360001_P01_FRONT-DOOR-UNIT_CAD (Autodesk Fusion 360 design; units mm, degrees)
part number: 2026-10-31-21-38-45-586
description: FRONT - DOOR LEAF - 4+4 LAMINATED | Tấm kính cửa 4+4 | P01
part number: 361001
description: FRONT - DOOR KICK STRIP | Thanh chân cửa nhôm | P01
part number: 361002
description: FRONT - GLAZING U-SEAL - BOHLE BO5201735 | Gioăng chữ U silicone | P01
part number: 368002
description: FRONT - DROP SEAL - ATHMER SCHALL-EX GSA 1-1112 | Ron chân cửa tự động | P01
part number: 368001
description: FRONT - DOOR HINGE - HOLD - H1 BOTTOM | Bản lề cửa dưới (chờ chọn) | P01
part number: 368101
description: FRONT - DOOR HINGE - HOLD - H2 MIDDLE | Bản lề cửa giữa (chờ chọn) | P01
description: FRONT - DOOR HINGE - HOLD - H3 TOP | Bản lề cửa trên (chờ chọn) | P01
description: FRONT - DOOR STRIKE - ENVELOPE | Đế hít cửa | P01
part number: 368102
description: FRONT - 180 MAGNETIC SEAL - HALF 2 OF 2 - HOLD | Gioăng nam châm 180° phía cửa (chờ chọn) | P01
part number: 368006
description: FRONT - DOOR PULL PAIR - HOLD | Tay nắm cửa (chờ chọn) | P01
part number: 368103
Autodesk Fusion 360 part; units mm, degrees
sketch "OUTLINE - DOOR LEAF (SKELETON TRAPEZOID + 25 MM INTO THE KICK STRIP)" plane through (0, 0, 0) normal (0, 1, 0) x (1, 0, 0) in component "361001 FRONT - DOOR LEAF - 4+4 LAMINATED"
  line L0 (-961, -80) -> (214, -80)
  line L1 (214, -80) -> (214, -105)
  line L2 (214, -105) -> (-67.7195, -2114)
  line L3 (-67.7195, -2114) -> (-961, -2114)
  line L4 (-961, -2114) -> (-961, -80)
  point P0 (-5000, 5000)
  dimension "d1096" = 5000
  dimension "d1097" = 5000
  dimension "d1098" = 5214
  dimension "d1099" = 4932.2805
  dimension "d1100" = 4039
  constraint vertical L1
  constraint vertical L4
  constraint horizontal L0
  constraint horizontal L3
  measures "d1096" horizontal distance of origin P0
  measures "d1097" vertical distance of origin P0
  measures "d1098" horizontal distance of L0.end P0
  measures "d1099" horizontal distance of L2.end P0
  measures "d1100" horizontal distance of L3.end P0
extrude "EXTRUDE - DOOR LEAF 8.76" add sketch "OUTLINE - DOOR LEAF (SKELETON TRAPEZOID + 25 MM INTO THE KICK STRIP)" along normal blind 8.76 from surface at -703.38 makes body 1 in component "361001 FRONT - DOOR LEAF - 4+4 LAMINATED"
sketch "SECTION - KICK STRIP (H: GLAZING POCKET OVER DROP-SEAL CAVITY)" plane through (0, 0, 0) normal (1, 0, 0) x (0, 0, -1) in component "361002 FRONT - DOOR KICK STRIP"
  line L0 (-20, -709) -> (-20, -705)
  line L1 (-20, -705) -> (-75, -705)
  line L2 (-75, -705) -> (-75, -693)
  line L3 (-75, -693) -> (-20, -693)
  line L4 (-20, -693) -> (-20, -689)
  line L5 (-20, -689) -> (-105, -689)
  line L6 (-105, -689) -> (-105, -693)
  line L7 (-105, -693) -> (-78, -693)
  line L8 (-78, -693) -> (-78, -705)
  line L9 (-78, -705) -> (-105, -705)
  line L10 (-105, -705) -> (-105, -709)
  line L11 (-105, -709) -> (-20, -709)
  point P0 (5000, -5000)
  dimension "d1107" = 5000
  dimension "d1108" = 5000
  dimension "d1115" = 4295
  dimension "d1116" = 4307
  dimension "d1117" = 4311
  dimension "d1118" = 4307
  dimension "d1119" = 4295
  dimension "d1120" = 4291
  constraint vertical L0
  constraint vertical L2
  constraint vertical L4
  constraint vertical L6
  constraint vertical L8
  constraint vertical L10
  constraint horizontal L1
  constraint horizontal L3
  constraint horizontal L5
  constraint horizontal L7
  constraint horizontal L9
  constraint horizontal L11
  measures "d1107" horizontal distance of origin P0
  measures "d1108" vertical distance of origin P0
  measures "d1115" vertical distance of L0.end P0
  measures "d1116" vertical distance of L2.end P0
  measures "d1117" vertical distance of L4.end P0
  measures "d1118" vertical distance of L6.end P0
  measures "d1119" vertical distance of L8.end P0
  measures "d1120" vertical distance of L10.end P0
extrude "EXTRUDE - KICK STRIP LENGTH" add sketch "SECTION - KICK STRIP (H: GLAZING POCKET OVER DROP-SEAL CAVITY)" along normal blind 1175 from surface at -961 separate body makes body 2 in component "361002 FRONT - DOOR KICK STRIP"
sketch "SECTION - KICK STRIP CHAMBER - OUTSIDE" plane through (0, 0, 0) normal (1, 0, 0) x (0, 0, -1) in component "361002 FRONT - DOOR KICK STRIP"
  line L0 (-21, -708) -> (-21, -706)
  line L1 (-21, -706) -> (-104, -706)
  line L2 (-104, -706) -> (-104, -708)
  line L3 (-104, -708) -> (-21, -708)
  point P0 (5000, -5000)
  dimension "d1124" = 5000
  dimension "d1125" = 5000
  dimension "d1128" = 4294
  dimension "d1129" = 4292
  constraint vertical L0
  constraint vertical L2
  constraint horizontal L1
  constraint horizontal L3
  measures "d1124" horizontal distance of origin P0
  measures "d1125" vertical distance of origin P0
  measures "d1128" vertical distance of L0.end P0
  measures "d1129" vertical distance of L2.end P0
extrude "CUT - KICK STRIP CHAMBER - OUTSIDE (D-85)" cut sketch "SECTION - KICK STRIP CHAMBER - OUTSIDE" along normal blind 1175 from surface at -961 bodies 2 in component "361002 FRONT - DOOR KICK STRIP"
sketch "SECTION - KICK STRIP CHAMBER - POD SIDE" plane through (0, 0, 0) normal (1, 0, 0) x (0, 0, -1) in component "361002 FRONT - DOOR KICK STRIP"
  line L0 (-21, -692) -> (-21, -690)
  line L1 (-21, -690) -> (-104, -690)
  line L2 (-104, -690) -> (-104, -692)
  line L3 (-104, -692) -> (-21, -692)
  point P0 (5000, -5000)
  dimension "d1133" = 5000
  dimension "d1134" = 5000
  dimension "d1137" = 4310
  dimension "d1138" = 4308
  constraint vertical L0
  constraint vertical L2
  constraint horizontal L1
  constraint horizontal L3
  measures "d1133" horizontal distance of origin P0
  measures "d1134" vertical distance of origin P0
  measures "d1137" vertical distance of L0.end P0
  measures "d1138" vertical distance of L2.end P0
extrude "CUT - KICK STRIP CHAMBER - POD SIDE (D-85)" cut sketch "SECTION - KICK STRIP CHAMBER - POD SIDE" along normal blind 1175 from surface at -961 bodies 2 in component "361002 FRONT - DOOR KICK STRIP"
sketch "SECTION - GLAZING U-SEAL" plane through (0, 0, 0) normal (1, 0, 0) x (0, 0, -1) in component "368002 FRONT - GLAZING U-SEAL - BOHLE BO5201735"
  line L0 (-78, -705) -> (-78, -693)
  line L1 (-78, -693) -> (-105, -693)
  line L2 (-105, -693) -> (-105, -694.62)
  line L3 (-105, -694.62) -> (-80, -694.62)
  line L4 (-80, -694.62) -> (-80, -703.38)
  line L5 (-80, -703.38) -> (-105, -703.38)
  line L6 (-105, -703.38) -> (-105, -705)
  line L7 (-105, -705) -> (-78, -705)
  point P0 (5000, -5000)
  dimension "d1142" = 5000
  dimension "d1143" = 5000
  dimension "d1148" = 4307
  dimension "d1149" = 4305.38
  dimension "d1150" = 4296.62
  dimension "d1151" = 4295
  constraint vertical L0
  constraint vertical L2
  constraint vertical L4
  constraint vertical L6
  constraint horizontal L1
  constraint horizontal L3
  constraint horizontal L5
  constraint horizontal L7
  measures "d1142" horizontal distance of origin P0
  measures "d1143" vertical distance of origin P0
  measures "d1148" vertical distance of L0.end P0
  measures "d1149" vertical distance of L2.end P0
  measures "d1150" vertical distance of L4.end P0
  measures "d1151" vertical distance of L6.end P0
extrude "EXTRUDE - GLAZING U-SEAL LENGTH" add sketch "SECTION - GLAZING U-SEAL" along normal blind 1175 from surface at -961 separate body makes body 3 in component "368002 FRONT - GLAZING U-SEAL - BOHLE BO5201735"
sketch "SECTION - DROP SEAL GSA 11.6 X 40" plane through (0, 0, 0) normal (1, 0, 0) x (0, 0, -1) in component "368001 FRONT - DROP SEAL - ATHMER SCHALL-EX GSA 1-1112"
  line L0 (-20, -704.6) -> (-20, -693)
  line L1 (-20, -693) -> (-60, -693)
  line L2 (-60, -693) -> (-60, -704.6)
  line L3 (-60, -704.6) -> (-20, -704.6)
  point P0 (5000, -5000)
  dimension "d1155" = 5000
  dimension "d1156" = 5000
  dimension "d1159" = 4307
  dimension "d1160" = 4295.4
  constraint vertical L0
  constraint vertical L2
  constraint horizontal L1
  constraint horizontal L3
  measures "d1155" horizontal distance of origin P0
  measures "d1156" vertical distance of origin P0
  measures "d1159" vertical distance of L0.end P0
  measures "d1160" vertical distance of L2.end P0
extrude "EXTRUDE - DROP SEAL CUT LENGTH" add sketch "SECTION - DROP SEAL GSA 11.6 X 40" along normal blind 1175 from surface at -961 separate body makes body 4 in component "368001 FRONT - DROP SEAL - ATHMER SCHALL-EX GSA 1-1112"
sketch "PLAN - HOLD HINGE SPACE H1" plane through (0, 0, 0) normal (0, 0, 1) x (1, 0, 0) in component "368101 FRONT - DOOR HINGE - HOLD - H1 BOTTOM"
  line L0 (-1132, -719) -> (-861, -719)
  line L1 (-861, -719) -> (-861, -679)
  line L2 (-861, -679) -> (-1132, -679)
  line L3 (-1132, -679) -> (-1132, -719)
  point P0 (-5000, -5000)
  dimension "d1164" = 5000
  dimension "d1165" = 5000
  dimension "d1166" = 4139
  dimension "d1167" = 3868
  dimension "d1168" = 4281
  dimension "d1169" = 4321
  constraint vertical L1
  constraint vertical L3
  constraint horizontal L0
  constraint horizontal L2
  measures "d1164" horizontal distance of origin P0
  measures "d1165" vertical distance of origin P0
  measures "d1166" horizontal distance of L0.end P0
  measures "d1167" horizontal distance of L2.end P0
  measures "d1168" vertical distance of L0.start P0
  measures "d1169" vertical distance of L1.end P0
extrude "EXTRUDE - H1" add sketch "PLAN - HOLD HINGE SPACE H1" along normal blind 120 from surface at 295 separate body makes body 5 in component "368101 FRONT - DOOR HINGE - HOLD - H1 BOTTOM"
sketch "PLAN - HOLD HINGE SPACE H2" plane through (0, 0, 0) normal (0, 0, 1) x (1, 0, 0) in component "368101 FRONT - DOOR HINGE - HOLD - H2 MIDDLE"
  line L0 (-1132, -719) -> (-861, -719)
  line L1 (-861, -719) -> (-861, -679)
  line L2 (-861, -679) -> (-1132, -679)
  line L3 (-1132, -679) -> (-1132, -719)
  point P0 (-5000, -5000)
  dimension "d1173" = 5000
  dimension "d1174" = 5000
  dimension "d1175" = 4139
  dimension "d1176" = 3868
  dimension "d1177" = 4281
  dimension "d1178" = 4321
  constraint vertical L1
  constraint vertical L3
  constraint horizontal L0
  constraint horizontal L2
  measures "d1173" horizontal distance of origin P0
  measures "d1174" vertical distance of origin P0
  measures "d1175" horizontal distance of L0.end P0
  measures "d1176" horizontal distance of L2.end P0
  measures "d1177" vertical distance of L0.start P0
  measures "d1178" vertical distance of L1.end P0
extrude "EXTRUDE - H2" add sketch "PLAN - HOLD HINGE SPACE H2" along normal blind 120 from surface at 1049.5 separate body makes body 6 in component "368101 FRONT - DOOR HINGE - HOLD - H2 MIDDLE"
sketch "PLAN - HOLD HINGE SPACE H3" plane through (0, 0, 0) normal (0, 0, 1) x (1, 0, 0) in component "368101 FRONT - DOOR HINGE - HOLD - H3 TOP"
  line L0 (-1132, -719) -> (-861, -719)
  line L1 (-861, -719) -> (-861, -679)
  line L2 (-861, -679) -> (-1132, -679)
  line L3 (-1132, -679) -> (-1132, -719)
  point P0 (-5000, -5000)
  dimension "d1182" = 5000
  dimension "d1183" = 5000
  dimension "d1184" = 4139
  dimension "d1185" = 3868
  dimension "d1186" = 4281
  dimension "d1187" = 4321
  constraint vertical L1
  constraint vertical L3
  constraint horizontal L0
  constraint horizontal L2
  measures "d1182" horizontal distance of origin P0
  measures "d1183" vertical distance of origin P0
  measures "d1184" horizontal distance of L0.end P0
  measures "d1185" horizontal distance of L2.end P0
  measures "d1186" vertical distance of L0.start P0
  measures "d1187" vertical distance of L1.end P0
extrude "EXTRUDE - H3" add sketch "PLAN - HOLD HINGE SPACE H3" along normal blind 120 from surface at 1804 separate body makes body 7 in component "368101 FRONT - DOOR HINGE - HOLD - H3 TOP"
sketch "PLAN - STRIKE" plane through (0, 0, 0) normal (0, 0, 1) x (1, 0, 0) in component "368102 FRONT - DOOR STRIKE - ENVELOPE"
  line L0 (-154.7195, -706.05) -> (-92.7195, -706.05)
  line L1 (-92.7195, -706.05) -> (-92.7195, -691.95)
  line L2 (-92.7195, -691.95) -> (-154.7195, -691.95)
  line L3 (-154.7195, -691.95) -> (-154.7195, -706.05)
  point P0 (-5000, -5000)
  dimension "d1191" = 5000
  dimension "d1192" = 5000
  dimension "d1193" = 4907.2805
  dimension "d1194" = 4845.2805
  dimension "d1195" = 4293.95
  dimension "d1196" = 4308.05
  constraint vertical L1
  constraint vertical L3
  constraint horizontal L0
  constraint horizontal L2
  measures "d1191" horizontal distance of origin P0
  measures "d1192" vertical distance of origin P0
  measures "d1193" horizontal distance of L0.end P0
  measures "d1194" horizontal distance of L2.end P0
  measures "d1195" vertical distance of L0.start P0
  measures "d1196" vertical distance of L1.end P0
extrude "EXTRUDE - STRIKE" add sketch "PLAN - STRIKE" along normal blind 23.5 from surface at 2092 separate body makes body 8 in component "368102 FRONT - DOOR STRIKE - ENVELOPE"
sketch "OUTLINE - 180 MAGNETIC SEAL DOOR HALF" plane through (0, 0, 0) normal (0, 1, 0) x (1, 0, 0) in component "368006 FRONT - 180 MAGNETIC SEAL - HALF 2 OF 2 - HOLD"
  line L0 (214, -105) -> (216.0196, -105)
  line L1 (216.0196, -105) -> (-65.7, -2114)
  line L2 (-65.7, -2114) -> (-67.7195, -2114)
  line L3 (-67.7195, -2114) -> (214, -105)
  point P0 (-5000, 5000)
  dimension "d1200" = 5000
  dimension "d1201" = 5000
  constraint horizontal L0
  constraint horizontal L2
  measures "d1200" horizontal distance of origin P0
  measures "d1201" vertical distance of origin P0
extrude "EXTRUDE - 180 MAGNETIC SEAL DOOR HALF" add sketch "OUTLINE - 180 MAGNETIC SEAL DOOR HALF" along normal blind 11.76 from surface at -704.88 separate body makes body 9 in component "368006 FRONT - 180 MAGNETIC SEAL - HALF 2 OF 2 - HOLD"
sketch "PLAN - PULL-OUT" plane through (0, 0, 0) normal (0, 0, 1) x (1, 0, 0) in component "368103 FRONT - DOOR PULL PAIR - HOLD"
  line L0 (-65.4401, -773.38) -> (-25.4401, -773.38)
  line L1 (-25.4401, -773.38) -> (-25.4401, -703.38)
  line L2 (-25.4401, -703.38) -> (-65.4401, -703.38)
  line L3 (-65.4401, -703.38) -> (-65.4401, -773.38)
  point P0 (-5000, -5000)
  dimension "d1211" = 5000
  dimension "d1212" = 5000
  dimension "d1213" = 4974.5599
  dimension "d1214" = 4934.5599
  dimension "d1215" = 4226.62
  dimension "d1216" = 4296.62
  constraint vertical L1
  constraint vertical L3
  constraint horizontal L0
  constraint horizontal L2
  measures "d1211" horizontal distance of origin P0
  measures "d1212" vertical distance of origin P0
  measures "d1213" horizontal distance of L0.end P0
  measures "d1214" horizontal distance of L2.end P0
  measures "d1215" vertical distance of L0.start P0
  measures "d1216" vertical distance of L1.end P0
extrude "EXTRUDE - PULL-OUT" add sketch "PLAN - PULL-OUT" along normal blind 360 from surface at 882 separate body makes body 10 in component "368103 FRONT - DOOR PULL PAIR - HOLD"
sketch "PLAN - PULL-IN" plane through (0, 0, 0) normal (0, 0, 1) x (1, 0, 0) in component "368103 FRONT - DOOR PULL PAIR - HOLD"
  line L0 (-65.4401, -694.62) -> (-25.4401, -694.62)
  line L1 (-25.4401, -694.62) -> (-25.4401, -624.62)
  line L2 (-25.4401, -624.62) -> (-65.4401, -624.62)
  line L3 (-65.4401, -624.62) -> (-65.4401, -694.62)
  point P0 (-5000, -5000)
  dimension "d1220" = 5000
  dimension "d1221" = 5000
  dimension "d1222" = 4974.5599
  dimension "d1223" = 4934.5599
  dimension "d1224" = 4305.38
  dimension "d1225" = 4375.38
  constraint vertical L1
  constraint vertical L3
  constraint horizontal L0
  constraint horizontal L2
  measures "d1220" horizontal distance of origin P0
  measures "d1221" vertical distance of origin P0
  measures "d1222" horizontal distance of L0.end P0
  measures "d1223" horizontal distance of L2.end P0
  measures "d1224" vertical distance of L0.start P0
  measures "d1225" vertical distance of L1.end P0
extrude "EXTRUDE - PULL-IN" add sketch "PLAN - PULL-IN" along normal blind 360 from surface at 882 separate body makes body 11 in component "368103 FRONT - DOOR PULL PAIR - HOLD"
component "361001 FRONT - DOOR LEAF - 4+4 LAMINATED" placed x (1, 0, 0) y (0, 1, 0) z (0, 0, 1) at (0, 0, 0)
component "361002 FRONT - DOOR KICK STRIP" placed x (1, 0, 0) y (0, 1, 0) z (0, 0, 1) at (0, 0, 0)
component "368002 FRONT - GLAZING U-SEAL - BOHLE BO5201735" placed x (1, 0, 0) y (0, 1, 0) z (0, 0, 1) at (0, 0, 0)
component "368001 FRONT - DROP SEAL - ATHMER SCHALL-EX GSA 1-1112" placed x (1, 0, 0) y (0, 1, 0) z (0, 0, 1) at (0, 0, 0)
component "368101 FRONT - DOOR HINGE - HOLD - H1 BOTTOM" placed x (1, 0, 0) y (0, 1, 0) z (0, 0, 1) at (0, 0, 0)
component "368101 FRONT - DOOR HINGE - HOLD - H2 MIDDLE" placed x (1, 0, 0) y (0, 1, 0) z (0, 0, 1) at (0, 0, 0)
component "368101 FRONT - DOOR HINGE - HOLD - H3 TOP" placed x (1, 0, 0) y (0, 1, 0) z (0, 0, 1) at (0, 0, 0)
component "368102 FRONT - DOOR STRIKE - ENVELOPE" placed x (1, 0, 0) y (0, 1, 0) z (0, 0, 1) at (0, 0, 0)
component "368006 FRONT - 180 MAGNETIC SEAL - HALF 2 OF 2 - HOLD" placed x (1, 0, 0) y (0, 1, 0) z (0, 0, 1) at (0, 0, 0)
component "368103 FRONT - DOOR PULL PAIR - HOLD" placed x (1, 0, 0) y (0, 1, 0) z (0, 0, 1) at (0, 0, 0)
equation "pod_w = 2500 mm" comment "SKELETON P04 DECIDED: D-01; conventions s4 (X = +-1250)"
equation "pod_d = 1700 mm" comment "SKELETON P04 DECIDED: D-01; conventions s4 (Y = +-850)"
equation "pod_h = 2400 mm" comment "SKELETON P04 DECIDED: D-21 (room floor to roof skin top)"
equation "glide_h = 10 mm" comment "SKELETON P04 ASSUMPTION: layout study inputs.py glide_h"
equation "band_h = 100 mm" comment "SKELETON P04 SOURCE: layout study B1 list B-BAND 100x40; inputs.py base_h"
equation "band_t = 40 mm" comment "SKELETON P04 SOURCE: layout study B1 list B-BAND 100x40"
equation "skin_t = 3 mm" comment "SKELETON P04 DECIDED: ACP skin, walls and ceiling (D-16; PM ruling 2026-10-31 on outer_t)"
equation "bond_t = 3 mm" comment "SKELETON P04 DECIDED: bond line between the ACP and the frame (PM ruling 2026-10-31 on outer_t)"
equation "frame_t = 40 mm" comment "SKELETON P04 DECIDED: aluminium frame tube depth, walls and ceiling (PM ruling 2026-10-31 on outer_t)"
equation "outer_t = skin_t + bond_t + frame_t" comment "SKELETON P04 DECIDED: PM ruling 2026-10-31: ACP 3 + bond line 3 + frame 40, walls and ceiling (was 43)"
equation "cav_gap = 4 mm" comment "SKELETON P04 DECIDED: D-16, D-42: the gap between the outer panel and the lining cassette in the wall and ceiling stack"
equation "cass_t = 34 mm" comment "SKELETON P04 SOURCE: layout study B1 final list L-CASS 34 (tray + 25 gap + felt 9)"
equation "stack_t = outer_t + cav_gap + cass_t" comment "SKELETON P04 CALCULATION: D-16, D-42 stack, walls and ceiling: outer panel + cavity gap + cassette (PM ruling 2026-10-31 on outer_t)"
equation "wall_depth = 1495 mm" comment "SKELETON P04 DECIDED: PM ruling pass C: side walls start at the decor back plate (Y -645), as v1 (1496)"
equation "lin_gap = 4 mm" comment "SKELETON P04 ASSUMPTION: PM ruling pass C: gap above the upper side linings so they stay floating (= the 4 mm stack gap)"
equation "seam_gap = 2.26 mm" comment "SKELETON P04 DECIDED: PM ruling 2026-10-31 (Mechanical Checker F-001, F-005): the Joints Engineer's 2.26 mm at all nine site seam types, set by a metal stop (1.5 stop washer + 0.76 rivnut head; joints register section 2.8)"
equation "mat_t = 3 mm" comment "SKELETON P04 DECIDED: D-72, PM ruling 2026-10-31 (from BASE): the 3 mm floor mat under the floor ply"
equation "floor_t = 9 mm" comment "SKELETON P04 DECIDED: PM ruling 2026-10-31: 9 mm floor panels (was 15, layout study B1 list), on the mat"
equation "thresh_h = 13 mm" comment "SKELETON P04 DECIDED: PM ruling 2026-10-31: 13 mm, a US-accessible threshold (D-18 had 20); the kick strip keeps its kick_gap above it"
equation "thresh_d = 60 mm" comment "SKELETON P04 SOURCE: layout study B1 list B-THRESH 1176 x 60 x 20"
equation "decor_d = 205 mm" comment "SKELETON P04 SOURCE: v1 geometry per the PM ruling on D-39 (as v1; the drawings win): v1 decor-frame drawing frames 191 (left) and 197 (right) deep plus ACP and back plate = the v1 STEP shell, Y -850 to -645 = 205. D-39 and the B1 list say 230-235 (v1 BOM); see BUILD-RECORD-P02"
equation "dl_w = 278 mm" comment "SKELETON P04 SOURCE: B1 list F-DL 278 (v1 BOM DL)"
equation "dr_w = 1016 mm" comment "SKELETON P04 SOURCE: B1 list F-DR 1016 (v1 STEP solid 78)"
equation "dt_w = 1697 mm" comment "SKELETON P04 SOURCE: B1 list F-DT 1697 (v1 BOM DT)"
equation "dt_h = 280 mm" comment "SKELETON P04 SOURCE: B1 list F-DT 280"
equation "door_w = 1176 mm" comment "SKELETON P04 DECIDED: D-46"
equation "door_h = 2011 mm" comment "SKELETON P04 SOURCE: B1 list F-GLASS-DOOR 2011; v1 STEP solid 238"
equation "glass_t = 8.76 mm" comment "SKELETON P04 DECIDED: D-46 (4+4 laminate)"
equation "glass_y = 699 mm" comment "SKELETON P04 SOURCE: v1 STEP solid 238 centre Y = -699 (layout study data)"
equation "kick_d = 20 mm" comment "SKELETON P04 ASSUMPTION: kick strip envelope depth (D-40 gives the height only)"
equation "kick_gap = 7 mm" comment "SKELETON P04 SOURCE: FRONT door unit: 7 mm running gap between the threshold and the kick strip for the drop seal (Mechanical Checker F-002 on P03)"
equation "fr_dz = 17 mm" comment "SKELETON P04 CALCULATION: v1 front top 2417 (v2 frame) - pod_h 2400"
equation "door_xl = 289 mm" comment "SKELETON P04 SOURCE: V1-FRONT-FACETS: door left edge X -961 = -1250 + 289"
equation "door_xbr = 1464 mm" comment "SKELETON P04 SOURCE: V1-FRONT-FACETS: door bottom-right X 214"
equation "door_xtr = 1182 mm" comment "SKELETON P04 SOURCE: V1-FRONT-FACETS: door top-right X -68"
equation "door_zb = 122 mm - fr_dz" comment "SKELETON P04 SOURCE: V1-FRONT-FACETS: door bottom Z 122"
equation "door_zt = 2133 mm - fr_dz" comment "SKELETON P04 SOURCE: V1-FRONT-FACETS: door top Z 2133"
equation "glass_gap = 4 mm" comment "SKELETON P04 DECIDED: PM ruling 2026-10-31 on Mechanical Checker F-014: the fixed glass's free edge runs parallel to the door's slanted edge, 4.0 mm away (FRONT's glass in PR #28 is the reference)"
equation "fix_xbr = 302 mm" comment "SKELETON P04 SOURCE: V1-FRONT-FACETS: fixed glass bottom-right X 948 = 1250 - 302"
equation "fix_xk = 501 mm" comment "SKELETON P04 SOURCE: V1-FRONT-FACETS: fixed glass knee X 749 = 1250 - 501"
equation "fix_zk = 1538 mm - fr_dz" comment "SKELETON P04 SOURCE: V1-FRONT-FACETS: fixed glass knee Z 1538"
equation "fix_xtr = 1480 mm" comment "SKELETON P04 SOURCE: V1-FRONT-FACETS: fixed glass top-right X 230 = -1250 + 1480"
equation "fix_zb = 119 mm - fr_dz" comment "SKELETON P04 SOURCE: V1-FRONT-FACETS: fixed glass bottom Z 119"
equation "fix_zt = 2136 mm - fr_dz" comment "SKELETON P04 SOURCE: V1-FRONT-FACETS: fixed glass top Z 2136"
equation "dt_zb = 2137 mm - fr_dz" comment "SKELETON P04 SOURCE: V1-FRONT-FACETS: DT and DR edge above the glass Z 2137"
equation "ch_zlo = 2217 mm - fr_dz" comment "SKELETON P04 SOURCE: V1-FRONT-FACETS: top chamfer front edge Z 2217 at Y -848"
equation "ch_yb = 672 mm" comment "SKELETON P04 SOURCE: V1-FRONT-FACETS: top chamfer back edge Y -672"
equation "dl_x2 = 92 mm" comment "SKELETON P04 SOURCE: V1-FRONT-FACETS: DL facet knee X -1158 = -1250 + 92"
equation "dl_y2 = 752 mm" comment "SKELETON P04 SOURCE: V1-FRONT-FACETS: DL facet knee Y -752"
equation "dl_x3 = 271 mm" comment "SKELETON P04 SOURCE: V1-FRONT-FACETS: DL front corner X -979"
equation "dl_y3 = 844 mm" comment "SKELETON P04 SOURCE: V1-FRONT-FACETS: DL front corner Y -844"
equation "dl_y1 = 670 mm" comment "SKELETON P04 SOURCE: V1-FRONT-FACETS: DL outer facet start Y -670"
equation "dl_zo = 2414 mm - fr_dz" comment "SKELETON P04 SOURCE: V1-FRONT-FACETS: DL top at the outer corner Z 2414"
equation "dt_x2 = 281 mm" comment "SKELETON P04 SOURCE: V1-FRONT-FACETS: DT lower facet left X -969 = -1250 + 281"
equation "dt_y2 = 767 mm" comment "SKELETON P04 SOURCE: V1-FRONT-FACETS: DT lower facet left Y -767"
equation "dt_y3 = 753 mm" comment "SKELETON P04 SOURCE: V1-FRONT-FACETS: DT lower facet outer Y -753 at X -1154"
equation "dr_xc = 198 mm" comment "SKELETON P04 SOURCE: V1-FRONT-FACETS: DR corner facet front X 1052 = 1250 - 198"
equation "dt_xr = 1699 mm" comment "SKELETON P04 SOURCE: V1-FRONT-FACETS: DT/DR joint at the top, X 449 = -1250 + 1699 (PM ruling pass C)"
equation "dr_yc = 672 mm" comment "SKELETON P04 SOURCE: V1-FRONT-FACETS: DR corner facet back Y -672"
equation "fix_xbl = door_xbr + ( door_zb - fix_zb ) * ( door_xbr - door_xtr ) / ( door_zt - door_zb ) + glass_gap * sqrt(( door_xbr - door_xtr ) * ( door_xbr - door_xtr ) + ( door_zt - door_zb ) * ( door_zt - door_zb )) / ( door_zt - door_zb )" comment "SKELETON P04 CALCULATION: F-014: fixed glass bottom-left, on the line glass_gap from the door's slanted edge (was v1's 1468)"
equation "fix_xtl = door_xbr + ( door_zb - fix_zt ) * ( door_xbr - door_xtr ) / ( door_zt - door_zb ) + glass_gap * sqrt(( door_xbr - door_xtr ) * ( door_xbr - door_xtr ) + ( door_zt - door_zb ) * ( door_zt - door_zb )) / ( door_zt - door_zb )" comment "SKELETON P04 CALCULATION: F-014: fixed glass top-left, on the same line (was v1's 1184)"
equation "floor_top = mat_t + floor_t" comment "SKELETON P04 CALCULATION: D-72: the floor top, Z 12 (mat 3 + ply 9); the threshold stands thresh_h above the room floor"
equation "wall_z0 = glide_h + band_h" comment "SKELETON P04 CALCULATION: base band top: glides + band"
equation "panel_z0 = wall_z0 + seam_gap" comment "SKELETON P04 CALCULATION: walls stand one seam_gap above the band top (joints register 2.8, IF-01)"
equation "wall_h = pod_h - wall_z0" comment "SKELETON P04 CALCULATION: 2290 = layout study v2_model wall_h"
equation "side_h = ( wall_h - 2 * seam_gap ) / 2" comment "SKELETON P04 CALCULATION: D-23: 2 sheets per side wall; the gap on the band and the horizontal seam (joints register 2.8)"
equation "side_l = wall_depth - seam_gap" comment "SKELETON P04 CALCULATION: side panel length along Y: the seam_gap at the decor's back plate (joints register 2.8, IF-07)"
equation "back_oh = pod_h - outer_t - seam_gap - panel_z0" comment "SKELETON P04 CALCULATION: PM ruling 2026-10-31 (pass D, F-004): the back outer frames run up to the ceiling frame (pod_h - outer_t), less the seam_gap under it, closing the slot at the back top edge"
equation "back_ph = ( back_oh - seam_gap ) / 2" comment "SKELETON P04 CALCULATION: D-23: 4 sheets on the back, two equal rows with one seam_gap between them (joints register 2.8); the lower back linings match the lower row, as on the side walls"
equation "half_pw = ( pod_w - 2 * outer_t - 3 * seam_gap ) / 2" comment "SKELETON P04 CALCULATION: SKIN width of each back and ceiling panel: two skins and three seam_gap seams between the side frames (F-001, joints register 2.8)"
equation "close_gap = 5.5 mm" comment "SKELETON P04 DECIDED: PM ruling 2026-10-31 (joints register, F-011/F-012): frame gap at the closing seams B1-B2, B3-B4 and C1-C2, which have no hard stop (slotted holes, thicker gasket)"
equation "half_fw = ( pod_w - 2 * outer_t - 2 * seam_gap - close_gap ) / 2" comment "SKELETON P04 CALCULATION: FRAME width of each back and ceiling panel: the skins overhang their frames by half_pw - half_fw at the closing seam (PM ruling 2026-10-31)"
equation "inner_w = pod_w - 2 * stack_t" comment "SKELETON P04 CALCULATION: inside width between the side linings"
equation "bolt_edge_inset = 220 mm" comment "SKELETON P04 DECIDED: PM ruling 2026-10-31: on every bolted edge the end bolts sit this far in from each panel end (the FRAME end, where the bolts go), the rest evenly spaced"
equation "spigot_inset = 100 mm" comment "SKELETON P04 DECIDED: PM ruling 2026-10-31: locating spigots this far in from each panel end (round hole at one end, slot at the other)"
equation "base_bolt_edge = bolt_edge_inset" comment "SKELETON P04 DECIDED: J-BASE-01 wall to band: the edge rule (kept by this name for parts already linked)"
equation "n_base_bolt = 4" comment "SKELETON P04 DECIDED: PM ruling 2026-10-31, J-BASE-01: bolts per panel along the band, evenly spaced"
equation "base_spigot_inset = spigot_inset" comment "SKELETON P04 DECIDED: J-BASE-01: the spigot rule (kept by this name for parts already linked)"
equation "base_side_y0 = pod_d / 2 - wall_depth + seam_gap" comment "SKELETON P04 CALCULATION: J-BASE-01: side bolt lines start at the side panel's front end (first bolt base_bolt_edge further on)"
equation "side_base_pitch = ( side_l - 2 * base_bolt_edge ) / ( n_base_bolt - 1 )" comment "SKELETON P04 CALCULATION: J-BASE-01 bolt pitch along a side panel"
equation "base_back_x0 = pod_w / 2 - outer_t - seam_gap" comment "SKELETON P04 CALCULATION: J-BASE-01: back bolt lines start at each back FRAME's outer end, X -/+ this (first bolt base_bolt_edge further in)"
equation "back_base_pitch = ( half_fw - 2 * base_bolt_edge ) / ( n_base_bolt - 1 )" comment "SKELETON P04 DECIDED: PM ruling 2026-10-31 (Reviewer 5 P2 on #58): J-BASE-01 pitch along a back panel, measured on the FRAME (half_fw), where the bolts go; 'panel end' means the frame end"
equation "ceil_bolt_z = pod_h - outer_t + frame_t / 2" comment "SKELETON P04 DECIDED: PM ruling 2026-10-31, J-CEIL-01 wall to ceiling: the bolt line on the ceiling frame's centre (Z 2374)"
equation "n_ceil_side_bolt = 4" comment "SKELETON P04 DECIDED: PM ruling 2026-10-31, J-CEIL-01: bolts along each side wall top"
equation "n_ceil_back_bolt = 4" comment "SKELETON P04 DECIDED: PM ruling 2026-10-31, J-CEIL-01: bolts along each back panel top, like the base (pitch about 253, every edge 350 or less; joints register: 82 bolts in all)"
equation "ceil_side_y0 = pod_d / 2 - wall_depth" comment "SKELETON P04 DECIDED: PM ruling 2026-10-31 (joints register): J-CEIL-01 side bolt lines start at Y -645, measured along the ceiling (first bolt bolt_edge_inset further on)"
equation "ceil_side_pitch = ( wall_depth - 2 * bolt_edge_inset ) / ( n_ceil_side_bolt - 1 )" comment "SKELETON P04 DECIDED: PM ruling 2026-10-31 (joints register): J-CEIL-01 pitch along a side wall top, over the ceiling's length (was over the side panel's)"
equation "ceil_back_x0 = pod_w / 2 - outer_t - seam_gap" comment "SKELETON P04 DECIDED: PM ruling 2026-10-31 (joints register): J-CEIL-01 back bolt lines start at each back frame's outer end, X -/+ this"
equation "ceil_back_pitch = ( half_fw - 2 * bolt_edge_inset ) / ( n_ceil_back_bolt - 1 )" comment "SKELETON P04 DECIDED: PM ruling 2026-10-31 (joints register): J-CEIL-01 pitch along a back panel top, on the frame (half_fw)"
equation "sk_ref = 5000 mm" comment "ASSUMPTION: sketch reference point offset: every sketch corner is dimensioned from a point at -sk_ref on both plane axes, so no dimension changes side when a corner crosses a pod centre line in an edit"
equation "fg_vis_zb = wall_z0" comment "CALCULATION: visible bottom of the fixed pane = the base band top (DL and DR stop there too, PM ruling 2026-10-31)"
equation "fg_vis_zt = dt_zb" comment "CALCULATION: visible top of the fixed pane = DT's underside"
equation "fg_gap = glass_gap" comment "CALCULATION: = the skeleton's glass_gap: the pane's free edge runs parallel to the door's latch edge, 4 mm off (PM ruling 2026-10-31; the skeleton's fix_xbl and fix_xtl follow the same rule since its update #58)"
equation "gu_prof_w = 15 mm" comment "SOURCE: Bohle BO5201571 aluminium U-profile 15 x 15 x 1.5 (hardware selection C5)"
equation "gu_prof_d = 15 mm" comment "SOURCE: as gu_prof_w"
equation "gu_prof_t = 1.5 mm" comment "SOURCE: as gu_prof_w"
equation "gu_w = gu_prof_w - 2 * gu_prof_t" comment "CALCULATION: inner width of the U-profile = the U-seal's outer width"
equation "gu_base = 2 mm" comment "ASSUMPTION: U-seal base under the glass edge; HOLD for Bohle's BO5201735 section drawing"
equation "gu_in_d = gu_prof_d - gu_prof_t" comment "CALCULATION: inner depth of the U-profile"
equation "fg_bite = gu_in_d - gu_base" comment "CALCULATION: glass cover in the hidden channels, 11.5 (PM ruling 2026-10-31); HOLD for the glass supplier's minimum"
equation "fg_r_len = sqrt(( fix_xbr - fix_xk ) * ( fix_xbr - fix_xk ) + ( fix_zk - fix_zb ) * ( fix_zk - fix_zb ))" comment "CALCULATION: length of the skeleton's right edge (bottom-right corner to the knee)"
equation "fg_rnx = ( fix_zk - fix_zb ) / fg_r_len" comment "CALCULATION: right edge outward normal, X"
equation "fg_rnz = ( fix_xk - fix_xbr ) / fg_r_len" comment "CALCULATION: right edge outward normal, Z"
equation "fg_rc = fg_rnx * ( pod_w / 2 - fix_xbr ) + fg_rnz * fix_zb" comment "CALCULATION: right edge line constant"
equation "fg_d_len = sqrt(( pod_w - fix_xtr - fix_xk ) * ( pod_w - fix_xtr - fix_xk ) + ( dt_zb - fix_zk ) * ( dt_zb - fix_zk ))" comment "CALCULATION: length of DR's diagonal inner edge (knee to DT's underside at X -pod_w/2 + fix_xtr)"
equation "fg_dnx = ( dt_zb - fix_zk ) / fg_d_len" comment "CALCULATION: diagonal outward normal, X"
equation "fg_dnz = ( pod_w - fix_xtr - fix_xk ) / fg_d_len" comment "CALCULATION: diagonal outward normal, Z"
equation "fg_dc = fg_dnx * ( pod_w / 2 - fix_xk ) + fg_dnz * fix_zk" comment "CALCULATION: diagonal line constant"
equation "fg_det = fg_rnx * fg_dnz - fg_rnz * fg_dnx" comment "CALCULATION: for the knee corner"
equation "fg_l_len = sqrt(( door_xbr - door_xtr ) * ( door_xbr - door_xtr ) + ( door_zt - door_zb ) * ( door_zt - door_zb ))" comment "CALCULATION: length of the door's latch edge"
equation "fg_lnx = ( door_zt - door_zb ) / fg_l_len" comment "CALCULATION: door latch edge normal toward the pane, X"
equation "fg_lnz = ( door_xbr - door_xtr ) / fg_l_len" comment "CALCULATION: door latch edge normal toward the pane, Z"
equation "fg_lc = fg_lnx * ( -pod_w / 2 + door_xbr ) + fg_lnz * door_zb" comment "CALCULATION: door latch edge line constant"
equation "door_glass_engage = 25 mm" comment "DECIDED: PM ruling on the FRONT plan, 2026-10-31: the glass runs 25 mm down into the kick strip, so the visible glass bottom stays at the skeleton's door_zb"
equation "kick_x0 = -pod_w / 2 + door_xl" comment "CALCULATION: strip end and leaf hinge edge = the skeleton door's left edge"
equation "kick_x1 = -pod_w / 2 + door_xbr" comment "CALCULATION: strip end under the latch edge = the skeleton door's bottom-right corner"
equation "kick_zb = thresh_h + kick_gap" comment "CALCULATION: strip bottom = threshold top + the skeleton's kick_gap (7, PM ruling)"
equation "door_top_cut = 2 mm" comment "DECIDED: PM ruling 2026-10-31: the leaf is 2 mm shorter at the top, so the gap to DT is 6 mm, inside the 5 to 10 mm the Sugatsune HT-MSG62 door-stop catch needs (datasheet)"
equation "leaf_zt = door_zt - door_top_cut" comment "CALCULATION: top of the leaf"
equation "kick_h = door_zb - kick_zb" comment "CALCULATION: strip height: 78 on skeleton P03"
equation "kick_len = kick_x1 - kick_x0" comment "CALCULATION: cut length of the strip and the drop seal"
equation "kick_pocket_d = door_glass_engage + gu_base" comment "CALCULATION: glazing pocket depth"
equation "kick_wall = ( kick_d - gu_w ) / 2" comment "CALCULATION: strip side walls: 4 with the skeleton's 20 mm kick_d (each a hollow wall, D-85)"
equation "kick_web = 3 mm" comment "ASSUMPTION: web between the glazing pocket and the drop-seal cavity"
equation "kick_skin = 1 mm" comment "ASSUMPTION: extrusion skin of the hollow side walls and their closing flanges (6063, 1.0 mm)"
equation "kick_ch_w = kick_wall - 2 * kick_skin" comment "CALCULATION: chamber inside each side wall: 2 mm"
equation "kick_cav_h = kick_h - kick_pocket_d - kick_web" comment "CALCULATION: drop-seal cavity height; must hold gsa_h"
equation "gsa_t = 11.6 mm" comment "SOURCE: athmer Schall-Ex GSA 1-1112 section 11.6 x 40 (hardware selection C4)"
equation "gsa_h = 40 mm" comment "SOURCE: athmer Schall-Ex GSA 1-1112 section 11.6 x 40 (hardware selection C4)"
equation "hinge_clamp_h = 120 mm" comment "ASSUMPTION: reserved height per hinge on the glass; HOLD H01 until a rated hinge is named"
equation "hinge_clamp_w = 100 mm" comment "ASSUMPTION: reserved width on the glass from its hinge edge; HOLD H01"
equation "hinge_clamp_t = 40 mm" comment "ASSUMPTION: reserved thickness across the glass; HOLD H01"
equation "hinge_pocket_d = 160 mm" comment "SOURCE: the HOLD candidate dormakaba OFFICE 11.233 needs a 160 mm frame pocket in DL (D-30, D-46; selection C1)"
equation "hinge_x0 = -pod_w / 2 + dl_w - hinge_pocket_d" comment "CALCULATION: inner end of the hinge pocket in DL (DL door face at XL + dl_w)"
equation "hinge_z1 = door_zb + 250 mm" comment "ASSUMPTION: bottom hinge centre 250 above the visible glass bottom; HOLD H01"
equation "hinge_z3 = leaf_zt - 250 mm" comment "ASSUMPTION: top hinge centre 250 below the glass top; HOLD H01"
equation "hinge_z2 = ( hinge_z1 + hinge_z3 ) / 2" comment "ASSUMPTION: middle hinge at mid-span; HOLD H01"
equation "lock_zc = floor_top + 1050 mm" comment "ASSUMPTION: pull centre 1050 above the finished floor (usual handle height); floor_top is the skeleton's floor on its mat"
equation "st_l = 62 mm" comment "SOURCE: Sugatsune HT-MSG62 strike plate, 62 long (datasheet D2, Dec 2020)"
equation "st_h = 22 mm" comment "SOURCE: strike plate, 22 down the glass faces (datasheet)"
equation "st_a = 14.1 mm" comment "SOURCE: strike HT-MSG62-U10 (10 mm glass), A = 14.1; on the 8.76 laminate with a 1.2 mm shim, HOLD (PM ruling)"
equation "st_top = 1.5 mm" comment "ASSUMPTION: strike plate over the glass top edge, steel plus packing"
equation "st_end = 25 mm" comment "ASSUMPTION: the strike's latch-side end, in from the leaf's top latch corner"
equation "ms_w = fg_gap / 2" comment "ASSUMPTION: the door's half of the 180 deg magnetic seal pair fills half the 4 mm gap"
equation "ms_t = 1.5 mm" comment "ASSUMPTION: the seal profile over each glass face"
equation "pull_cc = 300 mm" comment "SOURCE: HOLD candidate Häfele 903.10.390 pull pair, 300 mm centres, Ø19 (selection C2)"
equation "pull_len = pull_cc + 60 mm" comment "ASSUMPTION: bar 30 mm past each fixing"
equation "pull_w = 40 mm" comment "ASSUMPTION: reserved width: the Ø19 bar and its fixing roses"
equation "pull_stand = 70 mm" comment "ASSUMPTION: reserved projection from each glass face"
equation "pull_back = 100 mm" comment "ASSUMPTION: pull axis 100 mm in from the latch edge"
equation "pull_zc = lock_zc" comment "ASSUMPTION: pull centred at the lock height"
equation "pull_x = ( -pod_w / 2 + door_xbr - ( door_xbr - door_xtr ) * ( ( pull_zc + pull_len / 2 ) - door_zb ) / ( door_zt - door_zb ) ) - pull_back" comment "CALCULATION: pull axis X, measured from the latch edge at the bar's top end"
equation "d1096 = sk_ref"
equation "d1097 = sk_ref"
equation "d1098 = ( kick_x1 ) + sk_ref"
equation "d1099 = ( ( -pod_w / 2 + door_xbr - ( door_xbr - door_xtr ) * ( ( leaf_zt ) - door_zb ) / ( door_zt - door_zb ) ) ) + sk_ref"
equation "d1100 = ( kick_x0 ) + sk_ref"
equation "d1101 = ( door_zb - door_glass_engage ) + sk_ref"
equation "d1102 = ( door_zb ) + sk_ref"
equation "d1103 = ( leaf_zt ) + sk_ref"
equation "d1104 = ( -glass_y - glass_t / 2 ) * ( 1 )"
equation "d1105 = ( -glass_y + glass_t / 2 ) - ( -glass_y - glass_t / 2 )"
equation "d1107 = sk_ref"
equation "d1108 = sk_ref"
equation "d1109 = ( kick_zb ) + sk_ref"
equation "d1110 = ( kick_zb + kick_cav_h ) + sk_ref"
equation "d1111 = ( kick_zb ) + sk_ref"
equation "d1112 = ( door_zb ) + sk_ref"
equation "d1113 = ( door_zb - kick_pocket_d ) + sk_ref"
equation "d1114 = ( door_zb ) + sk_ref"
equation "d1115 = ( -glass_y - gu_w / 2 ) + sk_ref"
equation "d1116 = ( -glass_y + gu_w / 2 ) + sk_ref"
equation "d1117 = ( -glass_y + kick_d / 2 ) + sk_ref"
equation "d1118 = ( -glass_y + gu_w / 2 ) + sk_ref"
equation "d1119 = ( -glass_y - gu_w / 2 ) + sk_ref"
equation "d1120 = ( -glass_y - kick_d / 2 ) + sk_ref"
equation "d1121 = ( kick_x0 ) * ( 1 )"
equation "d1122 = ( kick_x1 ) - ( kick_x0 )"
equation "d1124 = sk_ref"
equation "d1125 = sk_ref"
equation "d1126 = ( kick_zb + kick_skin ) + sk_ref"
equation "d1127 = ( door_zb - kick_skin ) + sk_ref"
equation "d1128 = ( -glass_y - kick_d / 2 + kick_skin + kick_ch_w ) + sk_ref"
equation "d1129 = ( -glass_y - kick_d / 2 + kick_skin ) + sk_ref"
equation "d1130 = ( kick_x0 ) * ( 1 )"
equation "d1131 = ( kick_x1 ) - ( kick_x0 )"
equation "d1133 = sk_ref"
equation "d1134 = sk_ref"
equation "d1135 = ( kick_zb + kick_skin ) + sk_ref"
equation "d1136 = ( door_zb - kick_skin ) + sk_ref"
equation "d1137 = ( -glass_y + gu_w / 2 + kick_skin + kick_ch_w ) + sk_ref"
equation "d1138 = ( -glass_y + gu_w / 2 + kick_skin ) + sk_ref"
equation "d1139 = ( kick_x0 ) * ( 1 )"
equation "d1140 = ( kick_x1 ) - ( kick_x0 )"
equation "d1142 = sk_ref"
equation "d1143 = sk_ref"
equation "d1144 = ( door_zb - kick_pocket_d ) + sk_ref"
equation "d1145 = ( door_zb ) + sk_ref"
equation "d1146 = ( door_zb - door_glass_engage ) + sk_ref"
equation "d1147 = ( door_zb ) + sk_ref"
equation "d1148 = ( -glass_y + gu_w / 2 ) + sk_ref"
equation "d1149 = ( -glass_y + glass_t / 2 ) + sk_ref"
equation "d1150 = ( -glass_y - glass_t / 2 ) + sk_ref"
equation "d1151 = ( -glass_y - gu_w / 2 ) + sk_ref"
equation "d1152 = ( kick_x0 ) * ( 1 )"
equation "d1153 = ( kick_x1 ) - ( kick_x0 )"
equation "d1155 = sk_ref"
equation "d1156 = sk_ref"
equation "d1157 = ( kick_zb ) + sk_ref"
equation "d1158 = ( kick_zb + gsa_h ) + sk_ref"
equation "d1159 = ( -glass_y + gu_w / 2 ) + sk_ref"
equation "d1160 = ( -glass_y + gu_w / 2 - gsa_t ) + sk_ref"
equation "d1161 = ( kick_x0 ) * ( 1 )"
equation "d1162 = ( kick_x1 ) - ( kick_x0 )"
equation "d1164 = sk_ref"
equation "d1165 = sk_ref"
equation "d1166 = ( kick_x0 + hinge_clamp_w ) + sk_ref"
equation "d1167 = ( hinge_x0 ) + sk_ref"
equation "d1168 = ( -glass_y - hinge_clamp_t / 2 ) + sk_ref"
equation "d1169 = ( -glass_y + hinge_clamp_t / 2 ) + sk_ref"
equation "d1170 = ( hinge_z1 - hinge_clamp_h / 2 ) * ( 1 )"
equation "d1171 = ( hinge_z1 + hinge_clamp_h / 2 ) - ( hinge_z1 - hinge_clamp_h / 2 )"
equation "d1173 = sk_ref"
equation "d1174 = sk_ref"
equation "d1175 = ( kick_x0 + hinge_clamp_w ) + sk_ref"
equation "d1176 = ( hinge_x0 ) + sk_ref"
equation "d1177 = ( -glass_y - hinge_clamp_t / 2 ) + sk_ref"
equation "d1178 = ( -glass_y + hinge_clamp_t / 2 ) + sk_ref"
equation "d1179 = ( hinge_z2 - hinge_clamp_h / 2 ) * ( 1 )"
equation "d1180 = ( hinge_z2 + hinge_clamp_h / 2 ) - ( hinge_z2 - hinge_clamp_h / 2 )"
equation "d1182 = sk_ref"
equation "d1183 = sk_ref"
equation "d1184 = ( kick_x0 + hinge_clamp_w ) + sk_ref"
equation "d1185 = ( hinge_x0 ) + sk_ref"
equation "d1186 = ( -glass_y - hinge_clamp_t / 2 ) + sk_ref"
equation "d1187 = ( -glass_y + hinge_clamp_t / 2 ) + sk_ref"
equation "d1188 = ( hinge_z3 - hinge_clamp_h / 2 ) * ( 1 )"
equation "d1189 = ( hinge_z3 + hinge_clamp_h / 2 ) - ( hinge_z3 - hinge_clamp_h / 2 )"
equation "d1191 = sk_ref"
equation "d1192 = sk_ref"
equation "d1193 = ( ( ( -pod_w / 2 + door_xbr - ( door_xbr - door_xtr ) * ( ( leaf_zt ) - door_zb ) / ( door_zt - door_zb ) ) - st_end ) ) + sk_ref"
equation "d1194 = ( ( ( -pod_w / 2 + door_xbr - ( door_xbr - door_xtr ) * ( ( leaf_zt ) - door_zb ) / ( door_zt - door_zb ) ) - st_end ) - st_l ) + sk_ref"
equation "d1195 = ( -glass_y - st_a / 2 ) + sk_ref"
equation "d1196 = ( -glass_y + st_a / 2 ) + sk_ref"
equation "d1197 = ( leaf_zt - st_h ) * ( 1 )"
equation "d1198 = ( leaf_zt + st_top ) - ( leaf_zt - st_h )"
equation "d1200 = sk_ref"
equation "d1201 = sk_ref"
equation "d1202 = ( ( ( fg_lc - fg_lnz * ( door_zb ) ) / fg_lnx ) ) + sk_ref"
equation "d1203 = ( ( ( fg_lc + ms_w - fg_lnz * ( door_zb ) ) / fg_lnx ) ) + sk_ref"
equation "d1204 = ( ( ( fg_lc + ms_w - fg_lnz * ( leaf_zt ) ) / fg_lnx ) ) + sk_ref"
equation "d1205 = ( ( ( fg_lc - fg_lnz * ( leaf_zt ) ) / fg_lnx ) ) + sk_ref"
equation "d1206 = ( door_zb ) + sk_ref"
equation "d1207 = ( leaf_zt ) + sk_ref"
equation "d1208 = ( -glass_y - glass_t / 2 - ms_t ) * ( 1 )"
equation "d1209 = ( -glass_y + glass_t / 2 + ms_t ) - ( -glass_y - glass_t / 2 - ms_t )"
equation "d1211 = sk_ref"
equation "d1212 = sk_ref"
equation "d1213 = ( pull_x + pull_w / 2 ) + sk_ref"
equation "d1214 = ( pull_x - pull_w / 2 ) + sk_ref"
equation "d1215 = ( -glass_y - glass_t / 2 - pull_stand ) + sk_ref"
equation "d1216 = ( -glass_y - glass_t / 2 ) + sk_ref"
equation "d1217 = ( pull_zc - pull_len / 2 ) * ( 1 )"
equation "d1218 = ( pull_zc + pull_len / 2 ) - ( pull_zc - pull_len / 2 )"
equation "d1220 = sk_ref"
equation "d1221 = sk_ref"
equation "d1222 = ( pull_x + pull_w / 2 ) + sk_ref"
equation "d1223 = ( pull_x - pull_w / 2 ) + sk_ref"
equation "d1224 = ( -glass_y + glass_t / 2 ) + sk_ref"
equation "d1225 = ( -glass_y + glass_t / 2 + pull_stand ) + sk_ref"
equation "d1226 = ( pull_zc - pull_len / 2 ) * ( 1 )"
equation "d1227 = ( pull_zc + pull_len / 2 ) - ( pull_zc - pull_len / 2 )"
named bodies: "DOOR LEAF GLASS 4+4", "KICK STRIP", "GLAZING U-SEAL", "DROP SEAL ENVELOPE (CATALOGUE SECTION)", "HOLD HINGE SPACE H1", "HOLD HINGE SPACE H2", "HOLD HINGE SPACE H3", "FRONT - DOOR STRIKE - ENVELOPE", "180 MAGNETIC SEAL - DOOR HALF (HOLD PRODUCT)", "HOLD PULL SPACE - OUTSIDE", "HOLD PULL SPACE - POD SIDE"
